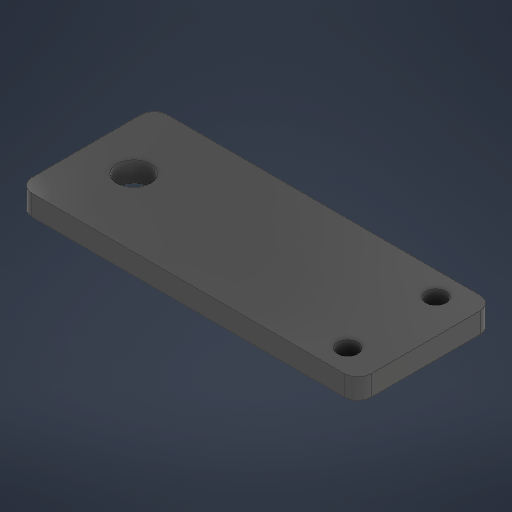
# Autodesk Inventor part: DragChainSupportMount
Saved by Autodesk Inventor 2027.1 (Build 311270010, 270A)
## iProperties
Created: 2026-10-20
Part Number: DragChainSupportMount
Material: MDF Medium Density Fiberboard
Document SubType Name: Modeling
Designer: SDS Scholar
Density: 0.8 g/cm^3
Appearance: Cardboard - Corrugated
Author: SDS Scholar
Autodesk Inventor part; units mm, degrees
ref_plane "YZ Plane" through (0, 0, 0) normal (1, 0, 0) x (0, 1, 0)
ref_plane "XZ Plane" through (0, 0, 0) normal (0, 1, 0) x (-1, 0, 0)
ref_plane "XY Plane" through (0, 0, 0) normal (0, 0, 1) x (1, 0, 0)
sketch "Sketch1" plane through (0, 0, 0) normal (0, 1, 0) x (-1, 0, 0)
  line L0 (25, 10) -> (-25, 10)
  line L1 (-25, 10) -> (-25, -10)
  line L2 (-25, -10) -> (25, -10)
  line L3 (25, -10) -> (25, 10)
  circle A0 centre (-20, -6.5) radius 1.5
  circle A1 centre (-20, 6.5) radius 1.5
  line L4 (25, 0) -> (-25, 0) construction
  circle A2 centre (18, 0) radius 2.5
  point P0 (0, 0)
  point P1 (0, -10)
  dimension "d0" = 50
  dimension "d1" = 20
  dimension "d13" = 3
  dimension "d14" = 3
  dimension "d15" = 10
  dimension "d16" = 5
  dimension "d17" = 5
  dimension "d18" = 7
  constraints: 10 end point, 3 centre point, 3 midpoint, 2 parallel, 2 perpendicular, 2 vertical alignment, 1 horizontal, 1 horizontal alignment, 1 point on line, 1 symmetric about line
  measures "d0" distance of L1.end L2.end
  measures "d1" distance of L0.end L1.end
  measures "d13" diameter of A0
  measures "d14" diameter of A1
  measures "d16" distance from line of L1 A0.centre
  measures "d17" diameter of A2
  measures "d18" distance from line of L3 A2.centre
extrude "Extrusion1" add sketch "Sketch1" along normal blind 3
fillet "Fillet1" radius 2 4 edges at (-25, 1.5, 10) (25, 1.5, 10) (25, 1.5, -10) (-25, 1.5, -10)
body "Solid1"
